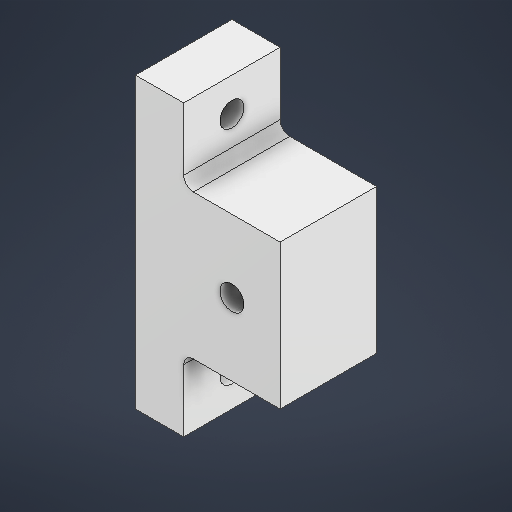
# Autodesk Inventor part: Acople caja 2
Saved by Autodesk Inventor 2027.1 (Build 311270010, 270A)
## iProperties
Created: 2026-10-01
Part Number: Acople caja 2
Material: Plástico ABS
Document SubType Name: Modeling
Designer: irene
Density: 1.06 g/cm^3
Appearance: Suave - Blanco
Author: irene
Autodesk Inventor part; units mm, degrees
ref_plane "YZ Plane" through (0, 0, 0) normal (1, 0, 0) x (0, 1, 0)
ref_plane "XZ Plane" through (0, 0, 0) normal (0, 1, 0) x (-1, 0, 0)
ref_plane "XY Plane" through (0, 0, 0) normal (0, 0, 1) x (1, 0, 0)
sketch "Boceto1" plane through (0, 0, 0) normal (1, 0, 0) x (0, 1, 0)
  line L0 (-30, -10) -> (30, -10)
  line L1 (30, -10) -> (30, 10)
  line L2 (30, 10) -> (-30, 10)
  line L3 (-30, 10) -> (-30, -10)
  line L4 (-30, -10) -> (30, 10) construction
  line L5 (30, -10) -> (-30, 10) construction
  point P0 (0, 0)
  dimension "d0" = 20
  dimension "d1" = 60
  constraints: 12 end point, 2 midpoint, 2 parallel, 1 horizontal, 1 perpendicular
  measures "d0" distance of L0.end L1.end
  measures "d1" distance of L1.end L2.end
extrude "Extrusión1" add sketch "Boceto1" along normal blind 10
sketch "Boceto2" plane through (10, 0, 0) normal (1, 0, 0) x (0, 0, -1)
  line L0 (10, 30) -> (-10, 30) projected
  line L1 (-10, 30) -> (0, 30)
  line L2 (0, 30) -> (0, -30)
  line L3 (0, -30) -> (-10, -30)
  line L4 (-10, -30) -> (-10, 30)
  line L5 (10, -30) -> (10, 30) projected
  line L6 (10, 30) -> (0, 30)
  line L7 (0, 30) -> (0, -30)
  line L8 (0, -30) -> (10, -30)
  line L9 (10, -30) -> (10, 30)
  point P0 (0, 0)
  dimension "d4" = 10
  dimension "d5" = 10
  constraints: 16 end point, 4 parallel, 2 midpoint, 2 perpendicular
  measures "d4" distance between parallel lines of L2 L4
  measures "d5" distance between parallel lines of L7 L5
extrude "Extrusión2" add sketch "Boceto2" along normal blind 20
sketch "Boceto4" plane through (30, 0, 0) normal (1, 0, 0) x (0, 0, -1)
  line L0 (10, 30) -> (-10, 30) projected
  line L1 (-10, 30) -> (-10, -30) projected
  line L2 (10, 30) -> (-10, 30)
  line L3 (-10, 30) -> (-10, 15)
  line L4 (-10, 15) -> (10, 15)
  line L5 (10, 15) -> (10, 30)
  line L6 (-10, -30) -> (10, -30) projected
  line L7 (10, -30) -> (-10, -30)
  line L8 (-10, -30) -> (-10, -15)
  line L9 (-10, -15) -> (10, -15)
  line L10 (10, -15) -> (10, -30)
  point P0 (0, 0)
  point P1 (4.5, 30)
  point P2 (-10, -15)
  point P3 (4.5, 30)
  dimension "d13" = 15
  dimension "d14" = 15
  constraints: 16 end point, 4 parallel, 3 perpendicular, 1 horizontal
  measures "d13" distance of L3.end L0.end
  measures "d14" distance of L1.end L8.end
extrude "Extrusión4" cut sketch "Boceto4" against normal up to surface (20 mm away)
sketch "Boceto6" plane through (0, -30, 10) normal (0, 0, 1) x (1, 0, 0)
  circle A0 centre (20, 30) radius 2.5
  line L0 (30, 45) -> (10, 45) projected
  line L1 (30, 45) -> (30, 15) projected
  point P0 (0, 30)
  dimension "d26" = 5
  dimension "d27" = 15
  dimension "d28" = 10
  constraints: 1 centre point
  measures "d26" diameter of A0
  measures "d27" distance from line of L0 A0.centre
  measures "d28" distance from line of L1 A0.centre
extrude "Extrusión6" cut sketch "Boceto6" against normal up to surface (20 mm away)
sketch "Boceto7" plane through (10, 15, 10) normal (1, 0, 0) x (0, 0, -1)
  circle A0 centre (10, 8) radius 2.5
  circle A1 centre (10, -38) radius 2.5
  line L0 (20, -30) -> (20, -45) projected
  line L1 (20, -45) -> (0, -45) projected
  line L2 (0, 15) -> (20, 15) projected
  line L3 (20, 15) -> (20, 0) projected
  point P0 (10, -15)
  dimension "d31" = 10
  dimension "d32" = 7
  dimension "d33" = 7
  dimension "d34" = 10
  dimension "d35" = 5
  dimension "d36" = 5
  constraints: 2 centre point
  measures "d31" distance from line of L0 A1.centre
  measures "d32" distance from line of L1 A1.centre
  measures "d33" distance from line of L2 A0.centre
  measures "d34" distance from line of L3 A0.centre
  measures "d35" diameter of A0
  measures "d36" diameter of A1
extrude "Extrusión7" cut sketch "Boceto7" against normal through all
fillet "Empalme2" radius 2 2 edges at (10, 15, 0) (10, -15, 0)
